Autodesk Fusion 360 part; units mm, degrees
(part 2 of 3)
extrude "Extrude3" add 1 faces at (382.2734, 175.5646, 1.3333) along direction (0, -1, 0) blind 29.5 on bodies 2 bodies 2
move_body "Move2" bodies 2 to x (-1, 0, 0) y (0, 1, 0) z (0, 0, -1) at (776.7286, 124.6532, 20.4334)
sketch "Sketch3" plane through (0, 0, 0) normal (0, 0, -1) x (1, 0, 0)
  line L0 (375, -270.5) -> (406, -270.5)
  line L1 (406, -270.5) -> (406, -300)
  line L2 (406, -300) -> (375, -300)
  line L3 (375, -300) -> (375, -270.5)
  line L4 (359, -316) -> (371, -316)
  line L5 (371, -316) -> (371, -313)
  line L6 (371, -313) -> (409, -313)
  line L7 (409, -313) -> (409, -316)
  line L8 (409, -316) -> (421, -316)
  line L9 (421, -316) -> (421, -319)
  line L10 (421, -319) -> (430, -319)
  line L11 (430, -319) -> (430, -322)
  line L12 (430, -322) -> (436, -322)
  line L13 (436, -322) -> (436, -325)
  line L14 (436, -325) -> (442, -325)
  line L15 (442, -325) -> (442, -328)
  line L16 (442, -328) -> (445, -328)
  line L17 (445, -328) -> (445, -331)
  line L18 (445, -331) -> (460, -331)
  line L19 (460, -331) -> (460, -328)
  line L20 (460, -328) -> (463, -328)
  line L21 (463, -328) -> (463, -325)
  line L22 (463, -325) -> (466, -325)
  line L23 (466, -325) -> (466, -319)
  line L24 (466, -319) -> (469, -319)
  line L25 (469, -319) -> (469, -310)
  line L26 (469, -310) -> (472, -310)
  line L27 (472, -310) -> (472, -307)
  line L28 (472, -307) -> (475, -307)
  line L29 (475, -307) -> (475, -304)
  line L30 (475, -304) -> (478, -304)
  line L31 (478, -304) -> (478, -298)
  line L32 (478, -298) -> (481, -298)
  line L33 (481, -298) -> (481, -289)
  line L34 (481, -289) -> (484, -289)
  line L35 (484, -289) -> (484, -277)
  line L36 (484, -277) -> (487, -277)
  line L37 (487, -277) -> (487, -256)
  line L38 (487, -256) -> (490, -256)
  line L39 (490, -256) -> (490, -238)
  line L40 (490, -238) -> (487, -238)
  line L41 (487, -238) -> (487, -229)
  line L42 (487, -229) -> (484, -229)
  line L43 (484, -229) -> (484, -226)
  line L44 (484, -226) -> (481, -226)
  line L45 (481, -226) -> (481, -223)
  line L46 (481, -223) -> (478, -223)
  line L47 (478, -223) -> (478, -220)
  line L48 (478, -220) -> (460, -220)
  line L49 (460, -220) -> (460, -223)
  line L50 (460, -223) -> (457, -223)
  line L51 (457, -223) -> (457, -226)
  line L52 (457, -226) -> (454, -226)
  line L53 (454, -226) -> (454, -229)
  line L54 (454, -229) -> (451, -229)
  line L55 (451, -229) -> (451, -232)
  line L56 (451, -232) -> (448, -232)
  line L57 (448, -232) -> (448, -238)
  line L58 (448, -238) -> (445, -238)
  line L59 (445, -238) -> (445, -244)
  line L60 (445, -244) -> (442, -244)
  line L61 (442, -244) -> (442, -247)
  line L62 (442, -247) -> (439, -247)
  line L63 (439, -247) -> (439, -250)
  line L64 (439, -250) -> (436, -250)
  line L65 (436, -250) -> (436, -253)
  line L66 (436, -253) -> (344, -253)
  line L67 (344, -253) -> (344, -250)
  line L68 (344, -250) -> (341, -250)
  line L69 (341, -250) -> (341, -247)
  line L70 (341, -247) -> (338, -247)
  line L71 (338, -247) -> (338, -244)
  line L72 (338, -244) -> (335, -244)
  line L73 (335, -244) -> (335, -238)
  line L74 (335, -238) -> (332, -238)
  line L75 (332, -238) -> (332, -232)
  line L76 (332, -232) -> (329, -232)
  line L77 (329, -232) -> (329, -229)
  line L78 (329, -229) -> (326, -229)
  line L79 (326, -229) -> (326, -226)
  line L80 (326, -226) -> (323, -226)
  line L81 (323, -226) -> (323, -223)
  line L82 (323, -223) -> (320, -223)
  line L83 (320, -223) -> (320, -220)
  line L84 (320, -220) -> (302, -220)
  line L85 (302, -220) -> (302, -223)
  line L86 (302, -223) -> (299, -223)
  line L87 (299, -223) -> (299, -226)
  line L88 (299, -226) -> (296, -226)
  line L89 (296, -226) -> (296, -229)
  line L90 (296, -229) -> (293, -229)
  line L91 (293, -229) -> (293, -238)
  line L92 (293, -238) -> (290, -238)
  line L93 (290, -238) -> (290, -256)
  line L94 (290, -256) -> (293, -256)
  line L95 (293, -256) -> (293, -277)
  line L96 (293, -277) -> (296, -277)
  line L97 (296, -277) -> (296, -289)
  line L98 (296, -289) -> (299, -289)
  line L99 (299, -289) -> (299, -298)
  line L100 (299, -298) -> (302, -298)
  line L101 (302, -298) -> (302, -304)
  line L102 (302, -304) -> (305, -304)
  line L103 (305, -304) -> (305, -307)
  line L104 (305, -307) -> (308, -307)
  line L105 (308, -307) -> (308, -310)
  line L106 (308, -310) -> (311, -310)
  line L107 (311, -310) -> (311, -319)
  line L108 (311, -319) -> (314, -319)
  line L109 (314, -319) -> (314, -325)
  line L110 (314, -325) -> (317, -325)
  line L111 (317, -325) -> (317, -328)
  line L112 (317, -328) -> (320, -328)
  line L113 (320, -328) -> (320, -331)
  line L114 (320, -331) -> (335, -331)
  line L115 (335, -331) -> (335, -328)
  line L116 (335, -328) -> (338, -328)
  line L117 (338, -328) -> (338, -325)
  line L118 (338, -325) -> (344, -325)
  line L119 (344, -325) -> (344, -322)
  line L120 (344, -322) -> (350, -322)
  line L121 (350, -322) -> (350, -319)
  line L122 (350, -319) -> (359, -319)
  line L123 (359, -319) -> (359, -316)
  line L124 (320, -260) -> (313.6403, -260)
  line L125 (313.6403, -260) -> (313.6403, -253.7)
  line L126 (313.6403, -253.7) -> (320, -253.7)
  line L127 (320, -253.7) -> (320, -260)
  line L128 (390.5, -209.9384) -> (390.5, -350) construction
  line L129 (461, -260) -> (467.3597, -260)
  line L130 (467.3597, -260) -> (467.3597, -253.7)
  line L131 (467.3597, -253.7) -> (461, -253.7)
  line L132 (461, -253.7) -> (461, -260)
  dimension "d11" = 6.3
  dimension "d12" = 6.3597
  constraint horizontal L124
  constraint vertical L125
  constraint horizontal L126
  constraint vertical L127
  constraint perpendicular L2 L128
  constraint symmetric L124.start L128 L129.start
  constraint symmetric L124.end L128 L129.end
  constraint symmetric L125.end L128 L130.end
  constraint symmetric L126.end L128 L131.end
  measures "d11" distance of L124.start L126.end
  measures "d12" distance of L124.start L124.end
extrude "Extrude4" cut sketch "Sketch3" against normal blind 4 contours L124 L125 L126 L127 | L129 L130 L131 L132 bodies 1
sketch "Sketch4" plane through (295.7884, 0, 0) normal (-1, 0, 0) x (0, -1, 0)
  line L0 (-277.2178, 20.4334) -> (-289.2178, 20.4334)
  line L1 (-289.2178, 20.4334) -> (-289.2178, 12.4334)
  line L2 (-289.2178, 12.4334) -> (-277.2178, 12.4334)
  line L3 (-277.2178, 12.4334) -> (-277.2178, 20.4334)
move_body "Move3" bodies 2 to x (1, 0, 0) y (0, 1, 0) z (0, 0, 1) at (0, 0, 25)
extrude "Extrude5" add 1 faces at (405.1218, 253.8845, 37.4334) along direction (0, 0, -1) blind 5 on bodies 2 bodies 2
sketch "Sketch5" plane through (0, 313.2178, 0) normal (0, 1, 0) x (-1, 0, 0)
  line L0 (-370.7884, 45.4334) -> (-408.7884, 45.4334)
  line L1 (-408.7884, 45.4334) -> (-408.7884, 32.4334)
  line L2 (-408.7884, 32.4334) -> (-370.7884, 32.4334)
  line L3 (-370.7884, 32.4334) -> (-370.7884, 45.4334)
  line L4 (-395, 40) -> (-386, 40)
  line L5 (-386, 40) -> (-386, 37)
  line L6 (-386, 37) -> (-395, 37)
  line L7 (-395, 37) -> (-395, 40)
  dimension "d17" = 3
  dimension "d18" = 9
  constraint horizontal L4
  constraint vertical L5
  constraint horizontal L6
  constraint vertical L7
  measures "d17" distance of L4.start L6.end
  measures "d18" distance of L4.start L4.end
extrude "Extrude6" cut sketch "Sketch5" against normal blind 4 contours L4 L5 L6 L7 bodies 2
fillet "Fillet1" radius 1.5 4 edges at (395, 312.7178, 37) (386, 312.7178, 37) (395, 312.7178, 40) (386, 312.7178, 40) on bodies 2
sketch "Sketch6" plane through (0, 0, 8) normal (0, 0, 1) x (-1, 0, 0)
  line L0 (-442, -328) -> (-442, -325)
  line L1 (-442, -325) -> (-436, -325)
  line L2 (-436, -325) -> (-436, -322)
  line L3 (-436, -322) -> (-430, -322)
  line L4 (-430, -322) -> (-430, -319)
  line L5 (-430, -319) -> (-421, -319)
  line L6 (-421, -319) -> (-421, -316)
  line L7 (-421, -316) -> (-409, -316)
  line L8 (-409, -316) -> (-409, -313)
  line L9 (-409, -313) -> (-371, -313)
  line L10 (-371, -313) -> (-371, -316)
  line L11 (-371, -316) -> (-359, -316)
  line L12 (-359, -316) -> (-359, -319)
  line L13 (-359, -319) -> (-350, -319)
  line L14 (-350, -319) -> (-350, -322)
  line L15 (-350, -322) -> (-344, -322)
  line L16 (-344, -322) -> (-344, -325)
  line L17 (-344, -325) -> (-338, -325)
  line L18 (-338, -325) -> (-338, -328)
  line L19 (-338, -328) -> (-335, -328)
  line L20 (-335, -328) -> (-335, -331)
  line L21 (-335, -331) -> (-320, -331)
  line L22 (-320, -331) -> (-320, -328)
  line L23 (-320, -328) -> (-317, -328)
  line L24 (-317, -328) -> (-317, -325)
  line L25 (-317, -325) -> (-314, -325)
  line L26 (-314, -325) -> (-314, -319)
  line L27 (-314, -319) -> (-311, -319)
  line L28 (-311, -319) -> (-311, -310)
  line L29 (-311, -310) -> (-308, -310)
  line L30 (-308, -310) -> (-308, -307)
  line L31 (-308, -307) -> (-305, -307)
  line L32 (-305, -307) -> (-305, -304)
  line L33 (-305, -304) -> (-302, -304)
  line L34 (-302, -304) -> (-302, -298)
  line L35 (-302, -298) -> (-299, -298)
  line L36 (-299, -298) -> (-299, -289)
  line L37 (-299, -289) -> (-296, -289)
  line L38 (-296, -289) -> (-296, -277)
  line L39 (-296, -277) -> (-293, -277)
  line L40 (-293, -277) -> (-293, -256)
  line L41 (-293, -256) -> (-290, -256)
  line L42 (-290, -256) -> (-290, -238)
  line L43 (-290, -238) -> (-293, -238)
  line L44 (-293, -238) -> (-293, -229)
  line L45 (-293, -229) -> (-296, -229)
  line L46 (-296, -229) -> (-296, -226)
  line L47 (-296, -226) -> (-299, -226)
  line L48 (-299, -226) -> (-299, -223)
  line L49 (-299, -223) -> (-302, -223)
  line L50 (-302, -223) -> (-302, -220)
  line L51 (-302, -220) -> (-320, -220)
  line L52 (-320, -220) -> (-320, -223)
  line L53 (-320, -223) -> (-323, -223)
  line L54 (-323, -223) -> (-323, -226)
  line L55 (-323, -226) -> (-326, -226)
  line L56 (-326, -226) -> (-326, -229)
  line L57 (-326, -229) -> (-329, -229)
  line L58 (-329, -229) -> (-329, -232)
  line L59 (-329, -232) -> (-332, -232)
  line L60 (-332, -232) -> (-332, -238)
  line L61 (-332, -238) -> (-335, -238)
  line L62 (-335, -238) -> (-335, -244)
  line L63 (-335, -244) -> (-338, -244)
  line L64 (-338, -244) -> (-338, -247)
  line L65 (-338, -247) -> (-341, -247)
  line L66 (-341, -247) -> (-341, -250)
  line L67 (-341, -250) -> (-344, -250)
  line L68 (-344, -250) -> (-344, -253)
  line L69 (-344, -253) -> (-436, -253)
  line L70 (-436, -253) -> (-436, -250)
  line L71 (-436, -250) -> (-439, -250)
  line L72 (-439, -250) -> (-439, -247)
  line L73 (-439, -247) -> (-442, -247)
  line L74 (-442, -247) -> (-442, -244)
  line L75 (-442, -244) -> (-445, -244)
  line L76 (-445, -244) -> (-445, -238)
  line L77 (-445, -238) -> (-448, -238)
  line L78 (-448, -238) -> (-448, -232)
  line L79 (-448, -232) -> (-451, -232)
  line L80 (-451, -232) -> (-451, -229)
  line L81 (-451, -229) -> (-454, -229)
  line L82 (-454, -229) -> (-454, -226)
  line L83 (-454, -226) -> (-457, -226)
  line L84 (-457, -226) -> (-457, -223)
  line L85 (-457, -223) -> (-460, -223)
  line L86 (-460, -223) -> (-460, -220)
  line L87 (-460, -220) -> (-478, -220)
  line L88 (-478, -220) -> (-478, -223)
  line L89 (-478, -223) -> (-481, -223)
  line L90 (-481, -223) -> (-481, -226)
  line L91 (-481, -226) -> (-484, -226)
  line L92 (-484, -226) -> (-484, -229)
  line L93 (-484, -229) -> (-487, -229)
  line L94 (-487, -229) -> (-487, -238)
  line L95 (-487, -238) -> (-490, -238)
  line L96 (-490, -238) -> (-490, -256)
  line L97 (-490, -256) -> (-487, -256)
  line L98 (-487, -256) -> (-487, -277)
  line L99 (-487, -277) -> (-484, -277)
  line L100 (-484, -277) -> (-484, -289)
  line L101 (-484, -289) -> (-481, -289)
  line L102 (-481, -289) -> (-481, -298)
  line L103 (-481, -298) -> (-478, -298)
  line L104 (-478, -298) -> (-478, -304)
  line L105 (-478, -304) -> (-475, -304)
  line L106 (-475, -304) -> (-475, -307)
  line L107 (-475, -307) -> (-472, -307)
  line L108 (-472, -307) -> (-472, -310)
  line L109 (-472, -310) -> (-469, -310)
  line L110 (-469, -310) -> (-469, -319)
  line L111 (-469, -319) -> (-466, -319)
  line L112 (-466, -319) -> (-466, -325)
  line L113 (-466, -325) -> (-463, -325)
  line L114 (-463, -325) -> (-463, -328)
  line L115 (-463, -328) -> (-460, -328)
  line L116 (-460, -328) -> (-460, -331)
  line L117 (-460, -331) -> (-445, -331)
  line L118 (-445, -331) -> (-445, -328)
  line L119 (-445, -328) -> (-442, -328)
  line L120 (-443, -324) -> (-443, -327)
  line L121 (-443, -327) -> (-446, -327)
  line L122 (-446, -327) -> (-446, -330)
  line L123 (-446, -330) -> (-459, -330)
  line L124 (-459, -330) -> (-459, -327)
  line L125 (-459, -327) -> (-462, -327)
  line L126 (-462, -327) -> (-462, -324)
  line L127 (-462, -324) -> (-465, -324)
  line L128 (-465, -324) -> (-465, -318)
  line L129 (-465, -318) -> (-468, -318)
  line L130 (-468, -318) -> (-468, -309)
  line L131 (-468, -309) -> (-471, -309)
  line L132 (-471, -309) -> (-471, -306)
  line L133 (-471, -306) -> (-474, -306)
  line L134 (-474, -306) -> (-474, -303)
  line L135 (-474, -303) -> (-477, -303)
  line L136 (-477, -303) -> (-477, -297)
  line L137 (-477, -297) -> (-480, -297)
  line L138 (-480, -297) -> (-480, -288)
  line L139 (-480, -288) -> (-483, -288)
  line L140 (-483, -288) -> (-483, -276)
  line L141 (-483, -276) -> (-486, -276)
  line L142 (-486, -276) -> (-486, -255)
  line L143 (-486, -255) -> (-489, -255)
  line L144 (-489, -255) -> (-489, -239)
  line L145 (-489, -239) -> (-486, -239)
  line L146 (-486, -239) -> (-486, -230)
  line L147 (-486, -230) -> (-483, -230)
  line L148 (-483, -230) -> (-483, -227)
  line L149 (-483, -227) -> (-480, -227)
  line L150 (-480, -227) -> (-480, -224)
  line L151 (-480, -224) -> (-477, -224)
  line L152 (-477, -224) -> (-477, -221)
  line L153 (-477, -221) -> (-461, -221)
  line L154 (-461, -221) -> (-461, -224)
  line L155 (-461, -224) -> (-458, -224)
  line L156 (-458, -224) -> (-458, -227)
  line L157 (-458, -227) -> (-455, -227)
  line L158 (-455, -227) -> (-455, -230)
  line L159 (-455, -230) -> (-452, -230)
  line L160 (-452, -230) -> (-452, -233)
  line L161 (-452, -233) -> (-449, -233)
  line L162 (-449, -233) -> (-449, -239)
  line L163 (-449, -239) -> (-446, -239)
  line L164 (-446, -239) -> (-446, -245)
  line L165 (-446, -245) -> (-443, -245)
  line L166 (-443, -245) -> (-443, -248)
  line L167 (-443, -248) -> (-440, -248)
  line L168 (-440, -248) -> (-440, -251)
  line L169 (-440, -251) -> (-437, -251)
  line L170 (-437, -251) -> (-437, -254)
  line L171 (-437, -254) -> (-343, -254)
  line L172 (-343, -254) -> (-343, -251)
  line L173 (-343, -251) -> (-340, -251)
  line L174 (-340, -251) -> (-340, -248)
  line L175 (-340, -248) -> (-337, -248)
  line L176 (-337, -248) -> (-337, -245)
  line L177 (-337, -245) -> (-334, -245)
  line L178 (-334, -245) -> (-334, -239)
  line L179 (-334, -239) -> (-331, -239)
  line L180 (-331, -239) -> (-331, -233)
  line L181 (-331, -233) -> (-328, -233)
  line L182 (-328, -233) -> (-328, -230)
  line L183 (-328, -230) -> (-325, -230)
  line L184 (-325, -230) -> (-325, -227)
  line L185 (-325, -227) -> (-322, -227)
  line L186 (-322, -227) -> (-322, -224)
  line L187 (-322, -224) -> (-319, -224)
  line L188 (-319, -224) -> (-319, -221)
  line L189 (-319, -221) -> (-303, -221)
  line L190 (-303, -221) -> (-303, -224)
  line L191 (-303, -224) -> (-300, -224)
  line L192 (-300, -224) -> (-300, -227)
  line L193 (-300, -227) -> (-297, -227)
  line L194 (-297, -227) -> (-297, -230)
  line L195 (-297, -230) -> (-294, -230)
  line L196 (-294, -230) -> (-294, -239)
  line L197 (-294, -239) -> (-291, -239)
  line L198 (-291, -239) -> (-291, -255)
  line L199 (-291, -255) -> (-294, -255)
  line L200 (-294, -255) -> (-294, -276)
  line L201 (-294, -276) -> (-297, -276)
  line L202 (-297, -276) -> (-297, -288)
  line L203 (-297, -288) -> (-300, -288)
  line L204 (-300, -288) -> (-300, -297)
  line L205 (-300, -297) -> (-303, -297)
  line L206 (-303, -297) -> (-303, -303)
  line L207 (-303, -303) -> (-306, -303)
  line L208 (-306, -303) -> (-306, -306)
  line L209 (-306, -306) -> (-309, -306)
  line L210 (-309, -306) -> (-309, -309)
  line L211 (-309, -309) -> (-312, -309)
  line L212 (-312, -309) -> (-312, -318)
  line L213 (-312, -318) -> (-315, -318)
  line L214 (-315, -318) -> (-315, -324)
  line L215 (-315, -324) -> (-318, -324)
  line L216 (-318, -324) -> (-318, -327)
  line L217 (-318, -327) -> (-321, -327)
  line L218 (-321, -327) -> (-321, -330)
  line L219 (-321, -330) -> (-334, -330)
  line L220 (-334, -330) -> (-334, -327)
  line L221 (-334, -327) -> (-337, -327)
  line L222 (-337, -327) -> (-337, -324)
  line L223 (-337, -324) -> (-343, -324)
  line L224 (-343, -324) -> (-343, -321)
  line L225 (-343, -321) -> (-349, -321)
  line L226 (-349, -321) -> (-349, -318)
  line L227 (-349, -318) -> (-358, -318)
  line L228 (-358, -318) -> (-358, -315)
  line L229 (-358, -315) -> (-370, -315)
  line L230 (-370, -315) -> (-370, -312)
  line L231 (-370, -312) -> (-410, -312)
  line L232 (-410, -312) -> (-410, -315)
  line L233 (-410, -315) -> (-422, -315)
  line L234 (-422, -315) -> (-422, -318)
  line L235 (-422, -318) -> (-431, -318)
  line L236 (-431, -318) -> (-431, -321)
  line L237 (-431, -321) -> (-437, -321)
  line L238 (-437, -321) -> (-437, -324)
  line L239 (-437, -324) -> (-443, -324)
  circle A0 centre (-290.8655, -267.5676) radius 1.5
  circle A1 centre (-290.8655, -267.5676) radius 2.3866
  dimension "d23" = 3
  constraint concentric A0 A1
  measures "d23" diameter of A0
extrude "Extrude7" add sketch "Sketch6" against normal blind 2 contours L40 A1 picked at (-292.7885, -267.5676) bodies 1
sketch "Sketch7" plane through (0, 0, 32.4334) normal (0, 0, -1) x (1, 0, 0)
  line L0 (337.7884, -328.2178) -> (337.7884, -325.2178)
  line L1 (337.7884, -325.2178) -> (343.7884, -325.2178)
  line L2 (343.7884, -325.2178) -> (343.7884, -322.2178)
  line L3 (343.7884, -322.2178) -> (349.7884, -322.2178)
  line L4 (349.7884, -322.2178) -> (349.7884, -319.2178)
  line L5 (349.7884, -319.2178) -> (358.7884, -319.2178)
  line L6 (358.7884, -319.2178) -> (358.7884, -316.2178)
  line L7 (358.7884, -316.2178) -> (370.7884, -316.2178)
  line L8 (370.7884, -316.2178) -> (370.7884, -313.2178)
  line L9 (370.7884, -313.2178) -> (408.7884, -313.2178)
  line L10 (408.7884, -313.2178) -> (408.7884, -316.2178)
  line L11 (408.7884, -316.2178) -> (420.7885, -316.2178)
  line L12 (420.7885, -316.2178) -> (420.7885, -319.2178)
  line L13 (420.7885, -319.2178) -> (429.7885, -319.2178)
  line L14 (429.7885, -319.2178) -> (429.7885, -322.2178)
  line L15 (429.7885, -322.2178) -> (435.7885, -322.2178)
  line L16 (435.7885, -322.2178) -> (435.7885, -325.2178)
  line L17 (435.7885, -325.2178) -> (441.7885, -325.2178)
  line L18 (441.7885, -325.2178) -> (441.7885, -328.2178)
  line L19 (441.7885, -328.2178) -> (444.7885, -328.2178)
  line L20 (444.7885, -328.2178) -> (444.7885, -331.2178)
  line L21 (444.7885, -331.2178) -> (459.7885, -331.2178)
  line L22 (459.7885, -331.2178) -> (459.7885, -328.2178)
  line L23 (459.7885, -328.2178) -> (462.7885, -328.2178)
  line L24 (462.7885, -328.2178) -> (462.7885, -325.2178)
  line L25 (462.7885, -325.2178) -> (465.7885, -325.2178)
  line L26 (465.7885, -325.2178) -> (465.7885, -319.2178)
  line L27 (465.7885, -319.2178) -> (468.7885, -319.2178)
  line L28 (468.7885, -319.2178) -> (468.7885, -310.2178)
  line L29 (468.7885, -310.2178) -> (471.7885, -310.2178)
  line L30 (471.7885, -310.2178) -> (471.7885, -307.2178)
  line L31 (471.7885, -307.2178) -> (474.7885, -307.2178)
  line L32 (474.7885, -307.2178) -> (474.7885, -304.2178)
  line L33 (474.7885, -304.2178) -> (477.7885, -304.2178)
  line L34 (477.7885, -304.2178) -> (477.7885, -298.2178)
  line L35 (477.7885, -298.2178) -> (480.7885, -298.2178)
  line L36 (480.7885, -298.2178) -> (480.7885, -289.2178)
  line L37 (480.7885, -289.2178) -> (483.7885, -289.2178)
  line L38 (483.7885, -289.2178) -> (483.7885, -277.2178)
  line L39 (483.7885, -277.2178) -> (486.7885, -277.2178)
  line L40 (486.7885, -277.2178) -> (486.7885, -256.2178)
  line L41 (486.7885, -256.2178) -> (489.7885, -256.2178)
  line L42 (489.7885, -256.2178) -> (489.7885, -238.2178)
  line L43 (489.7885, -238.2178) -> (486.7885, -238.2178)
  line L44 (486.7885, -238.2178) -> (486.7885, -229.2178)
  line L45 (486.7885, -229.2178) -> (483.7885, -229.2178)
  line L46 (483.7885, -229.2178) -> (483.7885, -226.2178)
  line L47 (483.7885, -226.2178) -> (480.7885, -226.2178)
  line L48 (480.7885, -226.2178) -> (480.7885, -223.2178)
  line L49 (480.7885, -223.2178) -> (477.7885, -223.2178)
  line L50 (477.7885, -223.2178) -> (477.7885, -220.2178)
  line L51 (477.7885, -220.2178) -> (459.7885, -220.2178)
  line L52 (459.7885, -220.2178) -> (459.7885, -223.2178)
  line L53 (459.7885, -223.2178) -> (456.7885, -223.2178)
  line L54 (456.7885, -223.2178) -> (456.7885, -226.2178)
  line L55 (456.7885, -226.2178) -> (453.7885, -226.2178)
  line L56 (453.7885, -226.2178) -> (453.7885, -229.2178)
  line L57 (453.7885, -229.2178) -> (450.7885, -229.2178)
  line L58 (450.7885, -229.2178) -> (450.7885, -232.2178)
  line L59 (450.7885, -232.2178) -> (447.7885, -232.2178)
  line L60 (447.7885, -232.2178) -> (447.7885, -238.2178)
  line L61 (447.7885, -238.2178) -> (444.7885, -238.2178)
  line L62 (444.7885, -238.2178) -> (444.7885, -244.2178)
  line L63 (444.7885, -244.2178) -> (441.7885, -244.2178)
  line L64 (441.7885, -244.2178) -> (441.7885, -247.2178)
  line L65 (441.7885, -247.2178) -> (438.7885, -247.2178)
  line L66 (438.7885, -247.2178) -> (438.7885, -250.2178)
  line L67 (438.7885, -250.2178) -> (435.7885, -250.2178)
  line L68 (435.7885, -250.2178) -> (435.7885, -253.2178)
  line L69 (435.7885, -253.2178) -> (343.7884, -253.2178)
  line L70 (343.7884, -253.2178) -> (343.7884, -250.2178)
  line L71 (343.7884, -250.2178) -> (340.7884, -250.2178)
  line L72 (340.7884, -250.2178) -> (340.7884, -247.2178)
  line L73 (340.7884, -247.2178) -> (337.7884, -247.2178)
  line L74 (337.7884, -247.2178) -> (337.7884, -244.2178)
  line L75 (337.7884, -244.2178) -> (334.7884, -244.2178)
  line L76 (334.7884, -244.2178) -> (334.7884, -238.2178)
  line L77 (334.7884, -238.2178) -> (331.7884, -238.2178)
  line L78 (331.7884, -238.2178) -> (331.7884, -232.2178)
  line L79 (331.7884, -232.2178) -> (328.7884, -232.2178)
  line L80 (328.7884, -232.2178) -> (328.7884, -229.2178)
  line L81 (328.7884, -229.2178) -> (325.7884, -229.2178)
  line L82 (325.7884, -229.2178) -> (325.7884, -226.2178)
  line L83 (325.7884, -226.2178) -> (322.7884, -226.2178)
  line L84 (322.7884, -226.2178) -> (322.7884, -223.2178)
  line L85 (322.7884, -223.2178) -> (319.7884, -223.2178)
  line L86 (319.7884, -223.2178) -> (319.7884, -220.2178)
  line L87 (319.7884, -220.2178) -> (301.7884, -220.2178)
  line L88 (301.7884, -220.2178) -> (301.7884, -223.2178)
  line L89 (301.7884, -223.2178) -> (298.7884, -223.2178)
  line L90 (298.7884, -223.2178) -> (298.7884, -226.2178)
  line L91 (298.7884, -226.2178) -> (295.7884, -226.2178)
  line L92 (295.7884, -226.2178) -> (295.7884, -229.2178)
  line L93 (295.7884, -229.2178) -> (292.7884, -229.2178)
  line L94 (292.7884, -229.2178) -> (292.7884, -238.2178)
  line L95 (292.7884, -238.2178) -> (289.7884, -238.2178)
  line L96 (289.7884, -238.2178) -> (289.7884, -256.2178)
  line L97 (289.7884, -256.2178) -> (292.7884, -256.2178)
  line L98 (292.7884, -256.2178) -> (292.7884, -277.2178)
  line L99 (292.7884, -277.2178) -> (295.7884, -277.2178)
  line L100 (295.7884, -277.2178) -> (295.7884, -289.2178)
  line L101 (295.7884, -289.2178) -> (298.7884, -289.2178)
  line L102 (298.7884, -289.2178) -> (298.7884, -298.2178)
  line L103 (298.7884, -298.2178) -> (301.7884, -298.2178)
  line L104 (301.7884, -298.2178) -> (301.7884, -304.2178)
  line L105 (301.7884, -304.2178) -> (304.7884, -304.2178)
  line L106 (304.7884, -304.2178) -> (304.7884, -307.2178)
  line L107 (304.7884, -307.2178) -> (307.7884, -307.2178)
  line L108 (307.7884, -307.2178) -> (307.7884, -310.2178)
  line L109 (307.7884, -310.2178) -> (310.7884, -310.2178)
  line L110 (310.7884, -310.2178) -> (310.7884, -319.2178)
  line L111 (310.7884, -319.2178) -> (313.7884, -319.2178)
  line L112 (313.7884, -319.2178) -> (313.7884, -325.2178)
  line L113 (313.7884, -325.2178) -> (316.7884, -325.2178)
  line L114 (316.7884, -325.2178) -> (316.7884, -328.2178)
  line L115 (316.7884, -328.2178) -> (319.7884, -328.2178)
  line L116 (319.7884, -328.2178) -> (319.7884, -331.2178)
  line L117 (319.7884, -331.2178) -> (334.7884, -331.2178)
  line L118 (334.7884, -331.2178) -> (334.7884, -328.2178)
  line L119 (334.7884, -328.2178) -> (337.7884, -328.2178)
  line L120 (336.7884, -324.2178) -> (336.7884, -327.2178)
  line L121 (336.7884, -327.2178) -> (333.7884, -327.2178)
  line L122 (333.7884, -327.2178) -> (333.7884, -330.2178)
  line L123 (333.7884, -330.2178) -> (320.7884, -330.2178)
  line L124 (320.7884, -330.2178) -> (320.7884, -327.2178)
  line L125 (320.7884, -327.2178) -> (317.7884, -327.2178)
  line L126 (317.7884, -327.2178) -> (317.7884, -324.2178)
  line L127 (317.7884, -324.2178) -> (314.7884, -324.2178)
  line L128 (314.7884, -324.2178) -> (314.7884, -318.2178)
  line L129 (314.7884, -318.2178) -> (311.7884, -318.2178)
  line L130 (311.7884, -318.2178) -> (311.7884, -309.2178)
  line L131 (311.7884, -309.2178) -> (308.7884, -309.2178)
  line L132 (308.7884, -309.2178) -> (308.7884, -306.2178)
  line L133 (308.7884, -306.2178) -> (305.7884, -306.2178)
  line L134 (305.7884, -306.2178) -> (305.7884, -303.2178)
  line L135 (305.7884, -303.2178) -> (302.7884, -303.2178)
  line L136 (302.7884, -303.2178) -> (302.7884, -297.2178)
  line L137 (302.7884, -297.2178) -> (299.7884, -297.2178)
  line L138 (299.7884, -297.2178) -> (299.7884, -288.2178)
  line L139 (299.7884, -288.2178) -> (296.7884, -288.2178)
  line L140 (296.7884, -288.2178) -> (296.7884, -276.2178)
  line L141 (296.7884, -276.2178) -> (293.7884, -276.2178)
  line L142 (293.7884, -276.2178) -> (293.7884, -255.2178)
  line L143 (293.7884, -255.2178) -> (290.7884, -255.2178)
  line L144 (290.7884, -255.2178) -> (290.7884, -239.2178)
  line L145 (290.7884, -239.2178) -> (293.7884, -239.2178)
  line L146 (293.7884, -239.2178) -> (293.7884, -230.2178)
  line L147 (293.7884, -230.2178) -> (296.7884, -230.2178)
  line L148 (296.7884, -230.2178) -> (296.7884, -227.2178)
  line L149 (296.7884, -227.2178) -> (299.7884, -227.2178)
  line L150 (299.7884, -227.2178) -> (299.7884, -224.2178)
  line L151 (299.7884, -224.2178) -> (302.7884, -224.2178)
  line L152 (302.7884, -224.2178) -> (302.7884, -221.2178)
  line L153 (302.7884, -221.2178) -> (318.7884, -221.2178)
  line L154 (318.7884, -221.2178) -> (318.7884, -224.2178)
  line L155 (318.7884, -224.2178) -> (321.7884, -224.2178)
  line L156 (321.7884, -224.2178) -> (321.7884, -227.2178)
  line L157 (321.7884, -227.2178) -> (324.7884, -227.2178)
  line L158 (324.7884, -227.2178) -> (324.7884, -230.2178)
  line L159 (324.7884, -230.2178) -> (327.7884, -230.2178)
  line L160 (327.7884, -230.2178) -> (327.7884, -233.2178)
  line L161 (327.7884, -233.2178) -> (330.7884, -233.2178)
  line L162 (330.7884, -233.2178) -> (330.7884, -239.2178)
  line L163 (330.7884, -239.2178) -> (333.7884, -239.2178)
  line L164 (333.7884, -239.2178) -> (333.7884, -245.2178)
  line L165 (333.7884, -245.2178) -> (336.7884, -245.2178)
  line L166 (336.7884, -245.2178) -> (336.7884, -248.2178)
  line L167 (336.7884, -248.2178) -> (339.7884, -248.2178)
  line L168 (339.7884, -248.2178) -> (339.7884, -251.2178)
  line L169 (339.7884, -251.2178) -> (342.7884, -251.2178)
  line L170 (342.7884, -251.2178) -> (342.7884, -254.2178)
  line L171 (342.7884, -254.2178) -> (436.7885, -254.2178)
  line L172 (436.7885, -254.2178) -> (436.7885, -251.2178)
  line L173 (436.7885, -251.2178) -> (439.7885, -251.2178)
  line L174 (439.7885, -251.2178) -> (439.7885, -248.2178)
  line L175 (439.7885, -248.2178) -> (442.7885, -248.2178)
  line L176 (442.7885, -248.2178) -> (442.7885, -245.2178)
  line L177 (442.7885, -245.2178) -> (445.7885, -245.2178)
  line L178 (445.7885, -245.2178) -> (445.7885, -239.2178)
  line L179 (445.7885, -239.2178) -> (448.7885, -239.2178)
  line L180 (448.7885, -239.2178) -> (448.7885, -233.2178)
  line L181 (448.7885, -233.2178) -> (451.7885, -233.2178)
  line L182 (451.7885, -233.2178) -> (451.7885, -230.2178)
  line L183 (451.7885, -230.2178) -> (454.7885, -230.2178)
  line L184 (454.7885, -230.2178) -> (454.7885, -227.2178)
  line L185 (454.7885, -227.2178) -> (457.7885, -227.2178)
  line L186 (457.7885, -227.2178) -> (457.7885, -224.2178)
  line L187 (457.7885, -224.2178) -> (460.7885, -224.2178)
  line L188 (460.7885, -224.2178) -> (460.7885, -221.2178)
  line L189 (460.7885, -221.2178) -> (476.7885, -221.2178)
  line L190 (476.7885, -221.2178) -> (476.7885, -224.2178)
  line L191 (476.7885, -224.2178) -> (479.7885, -224.2178)
  line L192 (479.7885, -224.2178) -> (479.7885, -227.2178)
  line L193 (479.7885, -227.2178) -> (482.7885, -227.2178)
  line L194 (482.7885, -227.2178) -> (482.7885, -230.2178)
  line L195 (482.7885, -230.2178) -> (485.7885, -230.2178)
  line L196 (485.7885, -230.2178) -> (485.7885, -239.2178)
  line L197 (485.7885, -239.2178) -> (488.7885, -239.2178)
  line L198 (488.7885, -239.2178) -> (488.7885, -255.2178)
  line L199 (488.7885, -255.2178) -> (485.7885, -255.2178)
  line L200 (485.7885, -255.2178) -> (485.7885, -276.2178)
  line L201 (485.7885, -276.2178) -> (482.7885, -276.2178)
  line L202 (482.7885, -276.2178) -> (482.7885, -288.2178)
  line L203 (482.7885, -288.2178) -> (479.7885, -288.2178)
  line L204 (479.7885, -288.2178) -> (479.7885, -297.2178)
  line L205 (479.7885, -297.2178) -> (476.7885, -297.2178)
  line L206 (476.7885, -297.2178) -> (476.7885, -303.2178)
  line L207 (476.7885, -303.2178) -> (473.7885, -303.2178)
  line L208 (473.7885, -303.2178) -> (473.7885, -306.2178)
  line L209 (473.7885, -306.2178) -> (470.7885, -306.2178)
  line L210 (470.7885, -306.2178) -> (470.7885, -309.2178)
  line L211 (470.7885, -309.2178) -> (467.7885, -309.2178)
  line L212 (467.7885, -309.2178) -> (467.7885, -318.2178)
  line L213 (467.7885, -318.2178) -> (464.7885, -318.2178)
  line L214 (464.7885, -318.2178) -> (464.7885, -324.2178)
  line L215 (464.7885, -324.2178) -> (461.7885, -324.2178)
  line L216 (461.7885, -324.2178) -> (461.7885, -327.2178)
  line L217 (461.7885, -327.2178) -> (458.7885, -327.2178)
  line L218 (458.7885, -327.2178) -> (458.7885, -330.2178)
  line L219 (458.7885, -330.2178) -> (445.7885, -330.2178)
  line L220 (445.7885, -330.2178) -> (445.7885, -327.2178)
  line L221 (445.7885, -327.2178) -> (442.7885, -327.2178)
  line L222 (442.7885, -327.2178) -> (442.7885, -324.2178)
  line L223 (442.7885, -324.2178) -> (436.7885, -324.2178)
  line L224 (436.7885, -324.2178) -> (436.7885, -321.2178)
  line L225 (436.7885, -321.2178) -> (430.7885, -321.2178)
  line L226 (430.7885, -321.2178) -> (430.7885, -318.2178)
  line L227 (430.7885, -318.2178) -> (421.7885, -318.2178)
  line L228 (421.7885, -318.2178) -> (421.7885, -315.2178)
  line L229 (421.7885, -315.2178) -> (409.7884, -315.2178)
  line L230 (409.7884, -315.2178) -> (409.7884, -312.2178)
  line L231 (409.7884, -312.2178) -> (369.7884, -312.2178)
  line L232 (369.7884, -312.2178) -> (369.7884, -315.2178)
  line L233 (369.7884, -315.2178) -> (357.7884, -315.2178)
  line L234 (357.7884, -315.2178) -> (357.7884, -318.2178)
  line L235 (357.7884, -318.2178) -> (348.7884, -318.2178)
  line L236 (348.7884, -318.2178) -> (348.7884, -321.2178)
  line L237 (348.7884, -321.2178) -> (342.7884, -321.2178)
  line L238 (342.7884, -321.2178) -> (342.7884, -324.2178)
  line L239 (342.7884, -324.2178) -> (336.7884, -324.2178)
  circle A0 centre (290.8949, -267.5741) radius 1.5
  circle A1 centre (290.8949, -267.5741) radius 2.3311
  dimension "d26" = 3
  constraint concentric A0 A1
  measures "d26" diameter of A0
extrude "Extrude8" add sketch "Sketch7" against normal blind 3 contours L98 A1 picked at (292.6572, -267.5741) bodies 2
sketch "Sketch8" plane through (0, 0, 8) normal (0, 0, 1) x (-1, 0, 0)
  circle A0 centre (-290.8655, -267.5676) radius 1.5
  line L0 (-442, -328) -> (-442, -325)
  line L1 (-442, -325) -> (-436, -325)
  line L2 (-436, -325) -> (-436, -322)
  line L3 (-436, -322) -> (-430, -322)
  line L4 (-430, -322) -> (-430, -319)
  line L5 (-430, -319) -> (-421, -319)
  line L6 (-421, -319) -> (-421, -316)
  line L7 (-421, -316) -> (-409, -316)
  line L8 (-409, -316) -> (-409, -313)
  line L9 (-409, -313) -> (-371, -313)
  line L10 (-371, -313) -> (-371, -316)
  line L11 (-371, -316) -> (-359, -316)
  line L12 (-359, -316) -> (-359, -319)
  line L13 (-359, -319) -> (-350, -319)
  line L14 (-350, -319) -> (-350, -322)
  line L15 (-350, -322) -> (-344, -322)
  line L16 (-344, -322) -> (-344, -325)
  line L17 (-344, -325) -> (-338, -325)
  line L18 (-338, -325) -> (-338, -328)
  line L19 (-338, -328) -> (-335, -328)
  line L20 (-335, -328) -> (-335, -331)
  line L21 (-335, -331) -> (-320, -331)
  line L22 (-320, -331) -> (-320, -328)
  line L23 (-320, -328) -> (-317, -328)
  line L24 (-317, -328) -> (-317, -325)
  line L25 (-317, -325) -> (-314, -325)
  line L26 (-314, -325) -> (-314, -319)
  line L27 (-314, -319) -> (-311, -319)
  line L28 (-311, -319) -> (-311, -310)
  line L29 (-311, -310) -> (-308, -310)
  line L30 (-308, -310) -> (-308, -307)
  line L31 (-308, -307) -> (-305, -307)
  line L32 (-305, -307) -> (-305, -304)
  line L33 (-305, -304) -> (-302, -304)
  line L34 (-302, -304) -> (-302, -298)
  line L35 (-302, -298) -> (-299, -298)
  line L36 (-299, -298) -> (-299, -289)
  line L37 (-299, -289) -> (-296, -289)
  line L38 (-296, -289) -> (-296, -277)
  line L39 (-296, -277) -> (-293, -277)
  line L40 (-293, -277) -> (-293, -268.6353)
  arc A1 (-293, -268.6353) -> (-293, -266.5) centre (-290.8655, -267.5676) ccw
  line L41 (-293, -266.5) -> (-293, -256)
  line L42 (-293, -256) -> (-290, -256)
  line L43 (-290, -256) -> (-290, -238)
  line L44 (-290, -238) -> (-293, -238)
  line L45 (-293, -238) -> (-293, -229)
  line L46 (-293, -229) -> (-296, -229)
  line L47 (-296, -229) -> (-296, -226)
  line L48 (-296, -226) -> (-299, -226)
  line L49 (-299, -226) -> (-299, -223)
  line L50 (-299, -223) -> (-302, -223)
  line L51 (-302, -223) -> (-302, -220)
  line L52 (-302, -220) -> (-320, -220)
  line L53 (-320, -220) -> (-320, -223)
  line L54 (-320, -223) -> (-323, -223)
  line L55 (-323, -223) -> (-323, -226)
  line L56 (-323, -226) -> (-326, -226)
  line L57 (-326, -226) -> (-326, -229)
  line L58 (-326, -229) -> (-329, -229)
  line L59 (-329, -229) -> (-329, -232)
  line L60 (-329, -232) -> (-332, -232)
  line L61 (-332, -232) -> (-332, -238)
  line L62 (-332, -238) -> (-335, -238)
  line L63 (-335, -238) -> (-335, -244)
  line L64 (-335, -244) -> (-338, -244)
  line L65 (-338, -244) -> (-338, -247)
  line L66 (-338, -247) -> (-341, -247)
  line L67 (-341, -247) -> (-341, -250)
  line L68 (-341, -250) -> (-344, -250)
  line L69 (-344, -250) -> (-344, -253)
  line L70 (-344, -253) -> (-436, -253)
  line L71 (-436, -253) -> (-436, -250)
  line L72 (-436, -250) -> (-439, -250)
  line L73 (-439, -250) -> (-439, -247)
  line L74 (-439, -247) -> (-442, -247)
  line L75 (-442, -247) -> (-442, -244)
  line L76 (-442, -244) -> (-445, -244)
  line L77 (-445, -244) -> (-445, -238)
  line L78 (-445, -238) -> (-448, -238)
  line L79 (-448, -238) -> (-448, -232)
  line L80 (-448, -232) -> (-451, -232)
  line L81 (-451, -232) -> (-451, -229)
  line L82 (-451, -229) -> (-454, -229)
  line L83 (-454, -229) -> (-454, -226)
  line L84 (-454, -226) -> (-457, -226)
  line L85 (-457, -226) -> (-457, -223)
  line L86 (-457, -223) -> (-460, -223)
  line L87 (-460, -223) -> (-460, -220)
  line L88 (-460, -220) -> (-478, -220)
  line L89 (-478, -220) -> (-478, -223)
  line L90 (-478, -223) -> (-481, -223)
  line L91 (-481, -223) -> (-481, -226)
  line L92 (-481, -226) -> (-484, -226)
  line L93 (-484, -226) -> (-484, -229)
  line L94 (-484, -229) -> (-487, -229)
  line L95 (-487, -229) -> (-487, -238)
  line L96 (-487, -238) -> (-490, -238)
  line L97 (-490, -238) -> (-490, -256)
  line L98 (-490, -256) -> (-487, -256)
  line L99 (-487, -256) -> (-487, -277)
  line L100 (-487, -277) -> (-484, -277)
  line L101 (-484, -277) -> (-484, -289)
  line L102 (-484, -289) -> (-481, -289)
  line L103 (-481, -289) -> (-481, -298)
  line L104 (-481, -298) -> (-478, -298)
  line L105 (-478, -298) -> (-478, -304)
  line L106 (-478, -304) -> (-475, -304)
  line L107 (-475, -304) -> (-475, -307)
  line L108 (-475, -307) -> (-472, -307)
  line L109 (-472, -307) -> (-472, -310)
  line L110 (-472, -310) -> (-469, -310)
  line L111 (-469, -310) -> (-469, -319)
  line L112 (-469, -319) -> (-466, -319)
  line L113 (-466, -319) -> (-466, -325)
  line L114 (-466, -325) -> (-463, -325)
  line L115 (-463, -325) -> (-463, -328)
  line L116 (-463, -328) -> (-460, -328)
  line L117 (-460, -328) -> (-460, -331)
  line L118 (-460, -331) -> (-445, -331)
  line L119 (-445, -331) -> (-445, -328)
  line L120 (-445, -328) -> (-442, -328)
  line L121 (-443, -324) -> (-443, -327)
  line L122 (-443, -327) -> (-446, -327)
  line L123 (-446, -327) -> (-446, -330)
  line L124 (-446, -330) -> (-459, -330)
  line L125 (-459, -330) -> (-459, -327)
  line L126 (-459, -327) -> (-462, -327)
  line L127 (-462, -327) -> (-462, -324)
  line L128 (-462, -324) -> (-465, -324)
  line L129 (-465, -324) -> (-465, -318)
  line L130 (-465, -318) -> (-468, -318)
  line L131 (-468, -318) -> (-468, -309)
  line L132 (-468, -309) -> (-471, -309)
  line L133 (-471, -309) -> (-471, -306)
  line L134 (-471, -306) -> (-474, -306)
  line L135 (-474, -306) -> (-474, -303)
  line L136 (-474, -303) -> (-477, -303)
  line L137 (-477, -303) -> (-477, -297)
  line L138 (-477, -297) -> (-480, -297)
  line L139 (-480, -297) -> (-480, -288)
  line L140 (-480, -288) -> (-483, -288)
  line L141 (-483, -288) -> (-483, -276)
  line L142 (-483, -276) -> (-486, -276)
  line L143 (-486, -276) -> (-486, -255)
  line L144 (-486, -255) -> (-489, -255)
  line L145 (-489, -255) -> (-489, -239)
  line L146 (-489, -239) -> (-486, -239)
  line L147 (-486, -239) -> (-486, -230)
  line L148 (-486, -230) -> (-483, -230)
  line L149 (-483, -230) -> (-483, -227)
  line L150 (-483, -227) -> (-480, -227)
  line L151 (-480, -227) -> (-480, -224)
  line L152 (-480, -224) -> (-477, -224)
  line L153 (-477, -224) -> (-477, -221)
  line L154 (-477, -221) -> (-461, -221)
  line L155 (-461, -221) -> (-461, -224)
  line L156 (-461, -224) -> (-458, -224)
  line L157 (-458, -224) -> (-458, -227)
  line L158 (-458, -227) -> (-455, -227)
  line L159 (-455, -227) -> (-455, -230)
  line L160 (-455, -230) -> (-452, -230)
  line L161 (-452, -230) -> (-452, -233)
  line L162 (-452, -233) -> (-449, -233)
  line L163 (-449, -233) -> (-449, -239)
  line L164 (-449, -239) -> (-446, -239)
  line L165 (-446, -239) -> (-446, -245)
  line L166 (-446, -245) -> (-443, -245)
  line L167 (-443, -245) -> (-443, -248)
  line L168 (-443, -248) -> (-440, -248)
  line L169 (-440, -248) -> (-440, -251)
  line L170 (-440, -251) -> (-437, -251)
  line L171 (-437, -251) -> (-437, -254)
  line L172 (-437, -254) -> (-343, -254)
  line L173 (-343, -254) -> (-343, -251)
  line L174 (-343, -251) -> (-340, -251)
  line L175 (-340, -251) -> (-340, -248)
  line L176 (-340, -248) -> (-337, -248)
  line L177 (-337, -248) -> (-337, -245)
  line L178 (-337, -245) -> (-334, -245)
  line L179 (-334, -245) -> (-334, -239)
  line L180 (-334, -239) -> (-331, -239)
  line L181 (-331, -239) -> (-331, -233)
  line L182 (-331, -233) -> (-328, -233)
  line L183 (-328, -233) -> (-328, -230)
  line L184 (-328, -230) -> (-325, -230)
  line L185 (-325, -230) -> (-325, -227)
  line L186 (-325, -227) -> (-322, -227)
  line L187 (-322, -227) -> (-322, -224)
  line L188 (-322, -224) -> (-319, -224)
  line L189 (-319, -224) -> (-319, -221)
  line L190 (-319, -221) -> (-303, -221)
  line L191 (-303, -221) -> (-303, -224)
  line L192 (-303, -224) -> (-300, -224)
  line L193 (-300, -224) -> (-300, -227)
  line L194 (-300, -227) -> (-297, -227)
  line L195 (-297, -227) -> (-297, -230)
  line L196 (-297, -230) -> (-294, -230)
  line L197 (-294, -230) -> (-294, -239)
  line L198 (-294, -239) -> (-291, -239)
  line L199 (-291, -239) -> (-291, -255)
  line L200 (-291, -255) -> (-294, -255)
  line L201 (-294, -255) -> (-294, -276)
  line L202 (-294, -276) -> (-297, -276)
  line L203 (-297, -276) -> (-297, -288)
  line L204 (-297, -288) -> (-300, -288)
  line L205 (-300, -288) -> (-300, -297)
  line L206 (-300, -297) -> (-303, -297)
  line L207 (-303, -297) -> (-303, -303)
  line L208 (-303, -303) -> (-306, -303)
  line L209 (-306, -303) -> (-306, -306)
  line L210 (-306, -306) -> (-309, -306)
  line L211 (-309, -306) -> (-309, -309)
  line L212 (-309, -309) -> (-312, -309)
  line L213 (-312, -309) -> (-312, -318)
  line L214 (-312, -318) -> (-315, -318)
  line L215 (-315, -318) -> (-315, -324)
  line L216 (-315, -324) -> (-318, -324)
  line L217 (-318, -324) -> (-318, -327)
  line L218 (-318, -327) -> (-321, -327)
  line L219 (-321, -327) -> (-321, -330)
  line L220 (-321, -330) -> (-334, -330)
  line L221 (-334, -330) -> (-334, -327)
  line L222 (-334, -327) -> (-337, -327)
  line L223 (-337, -327) -> (-337, -324)
  line L224 (-337, -324) -> (-343, -324)
  line L225 (-343, -324) -> (-343, -321)
  line L226 (-343, -321) -> (-349, -321)
  line L227 (-349, -321) -> (-349, -318)
  line L228 (-349, -318) -> (-358, -318)
  line L229 (-358, -318) -> (-358, -315)
  line L230 (-358, -315) -> (-370, -315)
  line L231 (-370, -315) -> (-370, -312)
  line L232 (-370, -312) -> (-410, -312)
  line L233 (-410, -312) -> (-410, -315)
  line L234 (-410, -315) -> (-422, -315)
  line L235 (-422, -315) -> (-422, -318)
  line L236 (-422, -318) -> (-431, -318)
  line L237 (-431, -318) -> (-431, -321)
  line L238 (-431, -321) -> (-437, -321)
  line L239 (-437, -321) -> (-437, -324)
  line L240 (-437, -324) -> (-443, -324)
  circle A2 centre (-488.7169, -265.5) radius 1.5
  circle A3 centre (-488.7169, -265.5) radius 2.2798
  dimension "d29" = 3
  constraint concentric A2 A3
  measures "d29" diameter of A2
extrude "Extrude9" add sketch "Sketch8" against normal blind 2 contours L99 A3 picked at (-490.7327, -265.5) bodies 1